Autodesk Fusion 360 part; units mm, degrees
(part 3 of 6)
sketch "Skizze5" plane through (0, 0, 0) normal (0, 1, 0) x (1, 0, 0)
  spline S0 degree 5 poles (100, -0.054) (99.9703, -0.0563) (99.9084, -0.0613) (99.8079, -0.0698) (99.6587, -0.0835) (99.4472, -0.1042) (99.2124, -0.1285) (98.957, -0.1559) (98.6857, -0.1861) (98.4034, -0.2184) (98.1151, -0.2525) (97.8247, -0.2876) (97.5347, -0.3237) (97.2456, -0.3604) (96.957, -0.3978) (96.6678, -0.4359) (96.3769, -0.4747) (96.0836, -0.5141) (95.788, -0.5542) (95.4904, -0.5949) (95.1918, -0.6361) (94.8927, -0.6777) (94.594, -0.7196) (94.2958, -0.7618) (93.9981, -0.8044) (93.7007, -0.8473) (93.4032, -0.8905) (93.1053, -0.9341) (92.8069, -0.978) (92.508, -1.0221) (92.2086, -1.0663) (91.9089, -1.1107) (91.6091, -1.1551) (91.3092, -1.1996) (91.0094, -1.244) (90.7096, -1.2886) (90.4099, -1.3332) (90.1102, -1.3779) (89.8105, -1.4227) (89.5107, -1.4676) (89.2109, -1.5126) (88.9111, -1.5576) (88.6111, -1.6025) (88.3111, -1.6473) (88.0111, -1.692) (87.711, -1.7366) (87.411, -1.7811) (87.1111, -1.8255) (86.8112, -1.8699) (86.5115, -1.9143) (86.2119, -1.9587) (85.9124, -2.003) (85.613, -2.0472) (85.3136, -2.0913) (85.0142, -2.1353) (84.7147, -2.179) (84.4152, -2.2226) (84.1157, -2.2661) (83.8162, -2.3094) (83.5167, -2.3526) (83.2173, -2.3957) (82.9178, -2.4387) (82.6184, -2.4816) (82.3189, -2.5243) (82.0196, -2.5668) (81.7202, -2.6092) (81.4208, -2.6513) (81.1215, -2.6933) (80.8222, -2.7352) (80.5229, -2.7769) (80.2237, -2.8184) (79.9245, -2.8598) (79.6253, -2.901) (79.3262, -2.9421) (79.027, -2.9829) (78.7278, -3.0236) (78.4286, -3.0639) (78.1294, -3.1041) (77.8302, -3.1439) (77.5309, -3.1835) (77.2316, -3.2228) (76.9322, -3.2619) (76.6329, -3.3007) (76.3335, -3.3393) (76.0342, -3.3777) (75.7348, -3.4159) (75.4355, -3.454) (75.1362, -3.4919) (74.8369, -3.5295) (74.5376, -3.567) (74.2382, -3.6042) (73.9389, -3.6412) (73.6395, -3.6778) (73.3402, -3.7141) (73.0407, -3.7501) (72.7413, -3.7859) (72.4419, -3.8214) (72.1425, -3.8568) (71.843, -3.8919) (71.5436, -3.9268) (71.2441, -3.9615) (70.9446, -3.9959) (70.6451, -4.0299) (70.3455, -4.0636) (70.0458, -4.097) (69.7461, -4.13) (69.4464, -4.1628) (69.1467, -4.1953) (68.8471, -4.2275) (68.5474, -4.2596) (68.2478, -4.2915) (67.9482, -4.3232) (67.6485, -4.3546) (67.3489, -4.3857) (67.0492, -4.4166) (66.7494, -4.4472) (66.4496, -4.4775) (66.1497, -4.5074) (65.8499, -4.5371) (65.5499, -4.5664) (65.25, -4.5954) (64.95, -4.6241) (64.65, -4.6525) (64.35, -4.6806) (64.05, -4.7084) (63.7499, -4.736) (63.4498, -4.7633) (63.1496, -4.7903) (62.8494, -4.8171) (62.5492, -4.8436) (62.249, -4.8699) (61.9487, -4.8959) (61.6484, -4.9216) (61.3481, -4.947) (61.0477, -4.972) (60.7474, -4.9968) (60.447, -5.0214) (60.1465, -5.0456) (59.8461, -5.0696) (59.5456, -5.0934) (59.245, -5.117) (58.9445, -5.1403) (58.6439, -5.1635) (58.3433, -5.1863) (58.0426, -5.2089) (57.742, -5.2312) (57.4414, -5.2531) (57.1408, -5.2747) (56.8401, -5.2959) (56.5395, -5.3169) (56.2388, -5.3376) (55.9381, -5.3581) (55.6373, -5.3784) (55.3364, -5.3985) (55.0355, -5.4183) (54.7346, -5.4379) (54.4336, -5.4572) (54.1326, -5.4762) (53.8316, -5.4949) (53.5305, -5.5134) (53.2295, -5.5315) (52.9284, -5.5494) (52.6274, -5.567) (52.3263, -5.5845) (52.0252, -5.6017) (51.7241, -5.6187) (51.4231, -5.6355) (51.122, -5.652) (50.8209, -5.6684) (50.5198, -5.6844) (50.2187, -5.7003) (49.9176, -5.7158) (49.6165, -5.7311) (49.3153, -5.746) (49.0141, -5.7607) (48.7129, -5.7751) (48.4116, -5.7892) (48.1104, -5.8031) (47.8091, -5.8168) (47.5078, -5.8303) (47.2065, -5.8435) (46.9052, -5.8565) (46.604, -5.8692) (46.3027, -5.8817) (46.0015, -5.8939) (45.7003, -5.9058) (45.3991, -5.9174) (45.0979, -5.9287) (44.7967, -5.9397) (44.4955, -5.9505) (44.1943, -5.961) (43.893, -5.9713) (43.5918, -5.9813) (43.2906, -5.9909) (42.9893, -6.0004) (42.6882, -6.0095) (42.387, -6.0183) (42.0858, -6.0269) (41.7847, -6.0352) (41.4836, -6.0433) (41.1824, -6.0511) (40.8813, -6.0587) (40.5801, -6.066) (40.2789, -6.0729) (39.9777, -6.0796) (39.6765, -6.0859) (39.3753, -6.0918) (39.0741, -6.0973) (38.773, -6.1025) (38.472, -6.1074) (38.171, -6.1119) (37.87, -6.1161) (37.5691, -6.1201) (37.2683, -6.1237) (36.9675, -6.1271) (36.6667, -6.1302) (36.366, -6.133) (36.0651, -6.1355) (35.7643, -6.1377) (35.4635, -6.1395) (35.1626, -6.141) (34.8617, -6.142) (34.5609, -6.1427) (34.2601, -6.1431) (33.9593, -6.143) (33.6586, -6.1425) (33.3579, -6.1416) (33.0573, -6.1404) (32.7568, -6.1387) (32.4563, -6.1367) (32.1559, -6.1344) (31.8555, -6.1316) (31.5551, -6.1285) (31.2547, -6.1251) (30.9543, -6.1212) (30.6539, -6.117) (30.3536, -6.1123) (30.0532, -6.1072) (29.753, -6.1018) (29.4528, -6.0959) (29.1527, -6.0895) (28.8527, -6.0828) (28.5528, -6.0756) (28.2529, -6.068) (27.9532, -6.0599) (27.6535, -6.0513) (27.3539, -6.0423) (27.0543, -6.0328) (26.7548, -6.0228) (26.4552, -6.0123) (26.1558, -6.0013) (25.8563, -5.9898) (25.5569, -5.9778) (25.2576, -5.9654) (24.9584, -5.9525) (24.6592, -5.9391) (24.3602, -5.9253) (24.0612, -5.9109) (23.7624, -5.8959) (23.4637, -5.8804) (23.1651, -5.8644) (22.8665, -5.8477) (22.5681, -5.8305) (22.2698, -5.8126) (21.9715, -5.7942) (21.6734, -5.7753) (21.3754, -5.7557) (21.0774, -5.7355) (20.7797, -5.7147) (20.482, -5.6932) (20.1846, -5.671) (19.8873, -5.6481) (19.5901, -5.6246) (19.2931, -5.6003) (18.9963, -5.5754) (18.6995, -5.5498) (18.4029, -5.5235) (18.1065, -5.4966) (17.8102, -5.469) (17.5142, -5.4407) (17.2183, -5.4117) (16.9227, -5.382) (16.6273, -5.3515) (16.3321, -5.3202) (16.0372, -5.288) (15.7425, -5.2549) (15.448, -5.2209) (15.1538, -5.1859) (14.8598, -5.1501) (14.5661, -5.1133) (14.2728, -5.0756) (13.9798, -5.0371) (13.6871, -4.9976) (13.3949, -4.9573) (13.103, -4.916) (12.8115, -4.8736) (12.5204, -4.8302) (12.2297, -4.7856) (11.9395, -4.7399) (11.6496, -4.693) (11.3603, -4.6448) (11.0714, -4.5954) (10.783, -4.5448) (10.4951, -4.493) (10.2078, -4.4398) (9.9211, -4.3854) (9.635, -4.3296) (9.3496, -4.2725) (9.0648, -4.2139) (8.7808, -4.1539) (8.4976, -4.0924) (8.2153, -4.0294) (7.9338, -3.9647) (7.6534, -3.8984) (7.3739, -3.8304) (7.0956, -3.7608) (6.8184, -3.6893) (6.5424, -3.6161) (6.2678, -3.541) (5.9946, -3.4641) (5.7231, -3.3853) (5.4534, -3.3045) (5.1857, -3.2217) (4.9202, -3.1368) (4.6572, -3.0499) (4.397, -2.9607) (4.14, -2.8693) (3.8864, -2.7758) (3.6367, -2.6801) (3.3914, -2.5824) (3.151, -2.4829) (2.9161, -2.3818) (2.6874, -2.2791) (2.4655, -2.1752) (2.2513, -2.07) (2.0455, -1.9637) (1.8488, -1.8566) (1.6618, -1.7492) (1.4847, -1.6421) (1.3178, -1.5359) (1.1612, -1.431) (1.0149, -1.327) (0.8788, -1.2233) (0.7528, -1.1197) (0.6367, -1.0169) (0.5301, -0.9168) (0.4329, -0.8201) (0.3448, -0.7236) (0.2659, -0.6222) (0.1959, -0.5179) (0.1349, -0.4238) (0.0831, -0.343) (0.0417, -0.2446) (0.0126, -0.1127) (-0.0013, -0.0224) (-0.001, -0.018) (0.0022, 0.06) (0.021, 0.1744) (0.0653, 0.2622) (0.1271, 0.3406) (0.1997, 0.4227) (0.2828, 0.5032) (0.3764, 0.5771) (0.4797, 0.647) (0.5918, 0.7165) (0.7127, 0.7861) (0.8428, 0.8551) (0.9827, 0.9229) (1.1327, 0.9898) (1.2933, 1.0565) (1.4646, 1.1233) (1.6468, 1.1901) (1.84, 1.2567) (2.0439, 1.3229) (2.2581, 1.3884) (2.4819, 1.4528) (2.7147, 1.5161) (2.9555, 1.5779) (3.2036, 1.6382) (3.458, 1.6968) (3.7179, 1.7536) (3.9826, 1.8086) (4.2513, 1.8617) (4.5235, 1.9129) (4.7987, 1.9623) (5.0764, 2.0098) (5.3563, 2.0557) (5.638, 2.0999) (5.9214, 2.1425) (6.2062, 2.1835) (6.4923, 2.2231) (6.7794, 2.2611) (7.0676, 2.2978) (7.3567, 2.3332) (7.6466, 2.3672) (7.9373, 2.4) (8.2287, 2.4315) (8.5207, 2.4619) (8.8133, 2.4912) (9.1065, 2.5193) (9.4001, 2.5464) (9.6942, 2.5725) (9.9887, 2.5976) (10.2836, 2.6218) (10.5789, 2.645) (10.8745, 2.6675) (11.1705, 2.6892) (11.4667, 2.7101) (11.7632, 2.7304) (12.06, 2.7499) (12.3571, 2.7687) (12.6543, 2.7867) (12.9518, 2.804) (13.2495, 2.8206) (13.5474, 2.8365) (13.8455, 2.8516) (14.1438, 2.8662) (14.4423, 2.8801) (14.7409, 2.8934) (15.0398, 2.9062) (15.3388, 2.9185) (15.6379, 2.9304) (15.9371, 2.9418) (16.2365, 2.9527) (16.5359, 2.9633) (16.8355, 2.9733) (17.1351, 2.983) (17.4349, 2.9921) (17.7347, 3.0008) (18.0347, 3.009) (18.3348, 3.0168) (18.6351, 3.0241) (18.9354, 3.031) (19.2358, 3.0375) (19.5364, 3.0436) (19.837, 3.0494) (20.1377, 3.0548) (20.4384, 3.0599) (20.7393, 3.0646) (21.0401, 3.0689) (21.3411, 3.0728) (21.642, 3.0764) (21.943, 3.0797) (22.2441, 3.0827) (22.5452, 3.0855) (22.8464, 3.0881) (23.1477, 3.0904) (23.449, 3.0924) (23.7503, 3.0941) (24.0517, 3.0954) (24.3531, 3.0964) (24.6546, 3.0971) (24.956, 3.0974) (25.2575, 3.0975) (25.5591, 3.0973) (25.8606, 3.097) (26.1622, 3.0966) (26.4639, 3.096) (26.7655, 3.0952) (27.0673, 3.0941) (27.369, 3.0927) (27.6708, 3.091) (27.9726, 3.089) (28.2745, 3.0867) (28.5764, 3.0841) (28.8783, 3.0814) (29.1802, 3.0785) (29.4821, 3.0755) (29.7841, 3.0724) (30.086, 3.0691) (30.388, 3.0656) (30.69, 3.062) (30.992, 3.058) (31.294, 3.0539) (31.596, 3.0495) (31.8981, 3.0449) (32.2001, 3.0402) (32.5022, 3.0353) (32.8043, 3.0303) (33.1064, 3.0251) (33.4086, 3.0198) (33.7107, 3.0142) (34.0129, 3.0084) (34.315, 3.0024) (34.6172, 2.9962) (34.9194, 2.9897) (35.2217, 2.9831) (35.5239, 2.9763) (35.8262, 2.9694) (36.1284, 2.9624) (36.4307, 2.9553) (36.733, 2.9481) (37.0353, 2.9407) (37.3377, 2.9333) (37.64, 2.9257) (37.9424, 2.9179) (38.2448, 2.91) (38.5472, 2.9019) (38.8496, 2.8937) (39.1519, 2.8853) (39.4543, 2.8767) (39.7567, 2.8679) (40.0591, 2.859) (40.3614, 2.8499) (40.6638, 2.8406) (40.9661, 2.8312) (41.2684, 2.8217) (41.5708, 2.812) (41.8731, 2.8023) (42.1755, 2.7926) (42.4779, 2.7828) (42.7804, 2.7729) (43.0828, 2.7628) (43.3853, 2.7526) (43.6877, 2.7422) (43.9902, 2.7316) (44.2926, 2.7207) (44.595, 2.7097) (44.8974, 2.6986) (45.1998, 2.6873) (45.5023, 2.6761) (45.8047, 2.6648) (46.1072, 2.6535) (46.4097, 2.6422) (46.7122, 2.6307) (47.0148, 2.6191) (47.3174, 2.6073) (47.62, 2.5953) (47.9226, 2.5832) (48.2252, 2.5709) (48.5278, 2.5586) (48.8303, 2.5462) (49.1329, 2.5338) (49.4355, 2.5214) (49.738, 2.5089) (50.0406, 2.4963) (50.3432, 2.4837) (50.6459, 2.4708) (50.9485, 2.4579) (51.2512, 2.4448) (51.5539, 2.4317) (51.8565, 2.4185) (52.1592, 2.4052) (52.4618, 2.3919) (52.7645, 2.3785) (53.0671, 2.3651) (53.3698, 2.3516) (53.6725, 2.338) (53.9752, 2.3242) (54.2779, 2.3103) (54.5806, 2.2963) (54.8834, 2.2823) (55.1861, 2.2681) (55.4889, 2.2539) (55.7916, 2.2397) (56.0944, 2.2254) (56.3971, 2.211) (56.6998, 2.1966) (57.0025, 2.182) (57.3052, 2.1674) (57.6079, 2.1527) (57.9106, 2.138) (58.2134, 2.1232) (58.5161, 2.1084) (58.8188, 2.0936) (59.1216, 2.0788) (59.4244, 2.0639) (59.7272, 2.049) (60.03, 2.034) (60.3329, 2.019) (60.6358, 2.0038) (60.9387, 1.9886) (61.2416, 1.9733) (61.5445, 1.9579) (61.8474, 1.9426) (62.1502, 1.9272) (62.4531, 1.9119) (62.7558, 1.8965) (63.0586, 1.881) (63.3614, 1.8655) (63.6642, 1.8498) (63.967, 1.8341) (64.2698, 1.8182) (64.5727, 1.8024) (64.8756, 1.7865) (65.1786, 1.7706) (65.4815, 1.7548) (65.7845, 1.739) (66.0875, 1.7233) (66.3905, 1.7075) (66.6935, 1.6916) (66.9964, 1.6757) (67.2993, 1.6596) (67.6021, 1.6435) (67.905, 1.6273) (68.2078, 1.611) (68.5107, 1.5946) (68.8136, 1.5782) (69.1165, 1.5619) (69.4195, 1.5455) (69.7225, 1.5291) (70.0255, 1.5127) (70.3284, 1.4964) (70.6314, 1.48) (70.9344, 1.4637) (71.2373, 1.4473) (71.5403, 1.4309) (71.8432, 1.4145) (72.1462, 1.3981) (72.4491, 1.3816) (72.7521, 1.365) (73.055, 1.3484) (73.358, 1.3318) (73.6609, 1.3151) (73.9638, 1.2984) (74.2667, 1.2816) (74.5697, 1.2649) (74.8726, 1.2481) (75.1757, 1.2314) (75.4787, 1.2146) (75.7818, 1.1979) (76.0848, 1.1812) (76.3879, 1.1645) (76.6909, 1.1477) (76.9938, 1.1309) (77.2968, 1.1141) (77.5997, 1.0972) (77.9026, 1.0803) (78.2055, 1.0633) (78.5085, 1.0462) (78.8116, 1.029) (79.1148, 1.0119) (79.4179, 0.9948) (79.7211, 0.9777) (80.0242, 0.9607) (80.3273, 0.9437) (80.6304, 0.9268) (80.9334, 0.9099) (81.2364, 0.893) (81.5394, 0.8761) (81.8424, 0.8591) (82.1455, 0.8421) (82.4485, 0.825) (82.7516, 0.8079) (83.0546, 0.7907) (83.3576, 0.7736) (83.6605, 0.7565) (83.9634, 0.7394) (84.2662, 0.7225) (84.569, 0.7056) (84.8718, 0.6888) (85.1746, 0.6721) (85.4774, 0.6555) (85.7802, 0.639) (86.083, 0.6224) (86.3857, 0.6059) (86.6884, 0.5894) (86.9911, 0.5729) (87.2937, 0.5565) (87.5962, 0.54) (87.8988, 0.5237) (88.2013, 0.5074) (88.5039, 0.4912) (88.8064, 0.4752) (89.1088, 0.4593) (89.4111, 0.4435) (89.7132, 0.4278) (90.0152, 0.4123) (90.3171, 0.3969) (90.619, 0.3816) (90.9208, 0.3665) (91.2228, 0.3515) (91.525, 0.3367) (91.8272, 0.322) (92.1294, 0.3075) (92.4314, 0.2932) (92.733, 0.2791) (93.0342, 0.2652) (93.3348, 0.2515) (93.6352, 0.2381) (93.9355, 0.2249) (94.2361, 0.212) (94.5372, 0.1993) (94.8388, 0.187) (95.1408, 0.175) (95.4424, 0.1633) (95.7428, 0.1521) (96.0413, 0.1412) (96.3374, 0.1308) (96.6311, 0.1209) (96.9232, 0.1115) (97.2149, 0.1027) (97.5075, 0.0944) (97.8012, 0.0868) (98.0954, 0.0797) (98.3877, 0.0734) (98.6739, 0.0678) (98.9487, 0.0631) (99.2071, 0.0593) (99.4444, 0.0564) (99.6576, 0.0545) (99.8076, 0.0538) (99.9084, 0.0537) (99.9703, 0.0539) (100, 0.054) knots 0 0 0 0 0 0 0.00142857 0.00285714 0.00428571 0.00571429 0.00714286 0.00857143 0.01 0.01142857 0.01285714 0.01428571 0.01571429 0.01714286 0.01857143 0.02 0.02142857 0.02285714 0.02428571 0.02571429 0.02714286 0.02857143 0.03 0.03142857 0.03285714 0.03428571 0.03571429 0.03714286 0.03857143 0.04 0.04142857 0.04285714 0.04428571 0.04571429 0.04714286 0.04857143 0.05 0.05142857 0.05285714 0.05428571 0.05571429 0.05714286 0.05857143 0.06 0.06142857 0.06285714 0.06428571 0.06571429 0.06714286 0.06857143 0.07 0.07142857 0.07285714 0.07428571 0.07571429 0.07714286 0.07857143 0.08 0.08142857 0.08285714 0.08428571 0.08571429 0.08714286 0.08857143 0.09 0.09142857 0.09285714 0.09428571 0.09571429 0.09714286 0.09857143 0.1 0.10142857 0.10285714 0.10428571 0.10571429 0.10714286 0.10857143 0.11 0.11142857 0.11285714 0.11428571 0.11571429 0.11714286 0.11857143 0.12 0.12142857 0.12285714 0.12428571 0.12571429 0.12714286 0.12857143 0.13 0.13142857 0.13285714 0.13428571 0.13571429 0.13714286 0.13857143 0.14 0.14142857 0.14285714 0.14428571 0.14571429 0.14714286 0.14857143 0.15 0.15142857 0.15285714 0.15428571 0.15571429 0.15714286 0.15857143 0.16 0.16142857 0.16285714 0.16428571 0.16571429 0.16714286 0.16857143 0.17 0.17142857 0.17285714 0.17428571 0.17571429 0.17714286 0.17857143 0.18 0.18142857 0.18285714 0.18428571 0.18571429 0.18714286 0.18857143 0.19 0.19142857 0.19285714 0.19428571 0.19571429 0.19714286 0.19857143 0.2 0.20142857 0.20285714 0.20428571 0.20571429 0.20714286 0.20857143 0.21 0.21142857 0.21285714 0.21428571 0.21571429 0.21714286 0.21857143 0.22 0.22142857 0.22285714 0.22428571 0.22571429 0.22714286 0.22857143 0.23 0.23142857 0.23285714 0.23428571 0.23571429 0.23714286 0.23857143 0.24 0.24142857 0.24285714 0.24428571 0.24571429 0.24714286 0.24857143 0.25 0.25142857 0.25285714 0.25428571 0.25571429 0.25714286 0.25857143 0.26 0.26142857 0.26285714 0.26428571 0.26571429 0.26714286 0.26857143 0.27 0.27142857 0.27285714 0.27428571 0.27571429 0.27714286 0.27857143 0.28 0.28142857 0.28285714 0.28428571 0.28571429 0.28714286 0.28857143 0.29 0.29142857 0.29285714 0.29428571 0.29571429 0.29714286 0.29857143 0.3 0.30142857 0.30285714 0.30428571 0.30571429 0.30714286 0.30857143 0.31 0.31142857 0.31285714 0.31428571 0.31571429 0.31714286 0.31857143 0.32 0.32142857 0.32285714 0.32428571 0.32571429 0.32714286 0.32857143 0.33 0.33142857 0.33285714 0.33428571 0.33571429 0.33714286 0.33857143 0.34 0.34142857 0.34285714 0.34428571 0.34571429 0.34714286 0.34857143 0.35 0.35142857 0.35285714 0.35428571 0.35571429 0.35714286 0.35857143 0.36 0.36142857 0.36285714 0.36428571 0.36571429 0.36714286 0.36857143 0.37 0.37142857 0.37285714 0.37428571 0.37571429 0.37714286 0.37857143 0.38 0.38142857 0.38285714 0.38428571 0.38571429 0.38714286 0.38857143 0.39 0.39142857 0.39285714 0.39428571 0.39571429 0.39714286 0.39857143 0.4 0.40142857 0.40285714 0.40428571 0.40571429 0.40714286 0.40857143 0.41 0.41142857 0.41285714 0.41428571 0.41571429 0.41714286 0.41857143 0.42 0.42142857 0.42285714 0.42428571 0.42571429 0.42714286 0.42857143 0.43 0.43142857 0.43285714 0.43428571 0.43571429 0.43714286 0.43857143 0.44 0.44142857 0.44285714 0.44428571 0.44571429 0.44714286 0.44857143 0.45 0.45142857 0.45285714 0.45428571 0.45571429 0.45714286 0.45857143 0.46 0.46142857 0.46285714 0.46428571 0.46571429 0.46714286 0.46857143 0.47 0.47142857 0.47285714 0.47428571 0.47571429 0.47714286 0.47857143 0.48 0.48142857 0.48285714 0.48428571 0.48571429 0.48714286 0.48857143 0.49 0.49142857 0.49285714 0.49428571 0.49571429 0.49714286 0.49857143 0.5 0.50142857 0.50285714 0.50428571 0.50571429 0.50714286 0.50857143 0.51 0.51142857 0.51285714 0.51428571 0.51571429 0.51714286 0.51857143 0.52 0.52142857 0.52285714 0.52428571 0.52571429 0.52714286 0.52857143 0.53 0.53142857 0.53285714 0.53428571 0.53571429 0.53714286 0.53857143 0.54 0.54142857 0.54285714 0.54428571 0.54571429 0.54714286 0.54857143 0.55 0.55142857 0.55285714 0.55428571 0.55571429 0.55714286 0.55857143 0.56 0.56142857 0.56285714 0.56428571 0.56571429 0.56714286 0.56857143 0.57 0.57142857 0.57285714 0.57428571 0.57571429 0.57714286 0.57857143 0.58 0.58142857 0.58285714 0.58428571 0.58571429 0.58714286 0.58857143 0.59 0.59142857 0.59285714 0.59428571 0.59571429 0.59714286 0.59857143 0.6 0.60142857 0.60285714 0.60428571 0.60571429 0.60714286 0.60857143 0.61 0.61142857 0.61285714 0.61428571 0.61571429 0.61714286 0.61857143 0.62 0.62142857 0.62285714 0.62428571 0.62571429 0.62714286 0.62857143 0.63 0.63142857 0.63285714 0.63428571 0.63571429 0.63714286 0.63857143 0.64 0.64142857 0.64285714 0.64428571 0.64571429 0.64714286 0.64857143 0.65 0.65142857 0.65285714 0.65428571 0.65571429 0.65714286 0.65857143 0.66 0.66142857 0.66285714 0.66428571 0.66571429 0.66714286 0.66857143 0.67 0.67142857 0.67285714 0.67428571 0.67571429 0.67714286 0.67857143 0.68 0.68142857 0.68285714 0.68428571 0.68571429 0.68714286 0.68857143 0.69 0.69142857 0.69285714 0.69428571 0.69571429 0.69714286 0.69857143 0.7 0.70142857 0.70285714 0.70428571 0.70571429 0.70714286 0.70857143 0.71 0.71142857 0.71285714 0.71428571 0.71571429 0.71714286 0.71857143 0.72 0.72142857 0.72285714 0.72428571 0.72571429 0.72714286 0.72857143 0.73 0.73142857 0.73285714 0.73428571 0.73571429 0.73714286 0.73857143 0.74 0.74142857 0.74285714 0.74428571 0.74571429 0.74714286 0.74857143 0.75 0.75142857 0.75285714 0.75428571 0.75571429 0.75714286 0.75857143 0.76 0.76142857 0.76285714 0.76428571 0.76571429 0.76714286 0.76857143 0.77 0.77142857 0.77285714 0.77428571 0.77571429 0.77714286 0.77857143 0.78 0.78142857 0.78285714 0.78428571 0.78571429 0.78714286 0.78857143 0.79 0.79142857 0.79285714 0.79428571 0.79571429 0.79714286 0.79857143 0.8 0.80142857 0.80285714 0.80428571 0.80571429 0.80714286 0.80857143 0.81 0.81142857 0.81285714 0.81428571 0.81571429 0.81714286 0.81857143 0.82 0.82142857 0.82285714 0.82428571 0.82571429 0.82714286 0.82857143 0.83 0.83142857 0.83285714 0.83428571 0.83571429 0.83714286 0.83857143 0.84 0.84142857 0.84285714 0.84428571 0.84571429 0.84714286 0.84857143 0.85 0.85142857 0.85285714 0.85428571 0.85571429 0.85714286 0.85857143 0.86 0.86142857 0.86285714 0.86428571 0.86571429 0.86714286 0.86857143 0.87 0.87142857 0.87285714 0.87428571 0.87571429 0.87714286 0.87857143 0.88 0.88142857 0.88285714 0.88428571 0.88571429 0.88714286 0.88857143 0.89 0.89142857 0.89285714 0.89428571 0.89571429 0.89714286 0.89857143 0.9 0.90142857 0.90285714 0.90428571 0.90571429 0.90714286 0.90857143 0.91 0.91142857 0.91285714 0.91428571 0.91571429 0.91714286 0.91857143 0.92 0.92142857 0.92285714 0.92428571 0.92571429 0.92714286 0.92857143 0.93 0.93142857 0.93285714 0.93428571 0.93571429 0.93714286 0.93857143 0.94 0.94142857 0.94285714 0.94428571 0.94571429 0.94714286 0.94857143 0.95 0.95142857 0.95285714 0.95428571 0.95571429 0.95714286 0.95857143 0.96 0.96142857 0.96285714 0.96428571 0.96571429 0.96714286 0.96857143 0.97 0.97142857 0.97285714 0.97428571 0.97571429 0.97714286 0.97857143 0.98 0.98142857 0.98285714 0.98428571 0.98571429 0.98714286 0.98857143 0.99 0.99142857 0.99285714 0.99428571 0.99571429 0.99714286 0.99857143 1 1 1 1 1 1
  line L0 (100, 0.054) -> (100, -0.054)
  point P0 (99.325, -0.117)
  point P1 (97.996, -0.267)
  point P2 (96.48, -0.461)
  point P3 (94.891, -0.678)
  point P4 (93.284, -0.908)
  point P5 (91.664, -1.147)
  point P6 (90.036, -1.389)
  point P7 (88.407, -1.633)
  point P8 (86.777, -1.875)
  point P9 (85.152, -2.115)
  point P10 (83.528, -2.351)
  point P11 (81.905, -2.583)
  point P12 (80.284, -2.81)
  point P13 (78.665, -3.032)
  point P14 (77.046, -3.247)
  point P15 (75.427, -3.455)
  point P16 (73.809, -3.657)
  point P17 (72.191, -3.851)
  point P18 (70.573, -4.038)
  point P19 (68.954, -4.216)
  point P20 (67.336, -4.387)
  point P21 (65.717, -4.55)
  point P22 (64.097, -4.704)
  point P23 (62.476, -4.85)
  point P24 (60.854, -4.988)
  point P25 (59.231, -5.118)
  point P26 (57.607, -5.241)
  point P27 (55.983, -5.355)
  point P28 (54.357, -5.462)
  point P29 (52.73, -5.561)
  point P30 (51.103, -5.653)
  point P31 (49.476, -5.738)
  point P32 (47.848, -5.815)
  point P33 (46.22, -5.885)
  point P34 (44.593, -5.947)
  point P35 (42.966, -6.001)
  point P36 (41.34, -6.047)
  point P37 (39.714, -6.085)
  point P38 (38.089, -6.113)
  point P39 (36.467, -6.132)
  point P40 (34.845, -6.142)
  point P41 (33.224, -6.141)
  point P42 (31.606, -6.129)
  point P43 (29.989, -6.106)
  point P44 (28.375, -6.071)
  point P45 (26.765, -6.023)
  point P46 (25.157, -5.961)
  point P47 (23.553, -5.885)
  point P48 (21.954, -5.793)
  point P49 (20.36, -5.684)
  point P50 (18.773, -5.556)
  point P51 (17.193, -5.409)
  point P52 (15.623, -5.241)
  point P53 (14.064, -5.048)
  point P54 (12.521, -4.83)
  point P55 (10.996, -4.582)
  point P56 (9.493, -4.301)
  point P57 (8.019, -3.984)
  point P58 (6.585, -3.627)
  point P59 (5.208, -3.228)
  point P60 (3.924, -2.789)
  point P61 (2.793, -2.326)
  point P62 (1.888, -1.877)
  point P63 (1.237, -1.481)
  point P64 (0.791, -1.15)
  point P65 (0.486, -0.872)
  point P66 (0.275, -0.631)
  point P67 (0.131, -0.417)
  point P68 (0.04, -0.221)
  point P69 (0.002, -0.041)
  point P70 (0.018, 0.135)
  point P71 (0.104, 0.309)
  point P72 (0.257, 0.476)
  point P73 (0.476, 0.643)
  point P74 (0.778, 0.82)
  point P75 (1.202, 1.018)
  point P76 (1.82, 1.249)
  point P77 (2.714, 1.515)
  point P78 (3.89, 1.789)
  point P79 (5.256, 2.039)
  point P80 (6.72, 2.253)
  point P81 (8.236, 2.432)
  point P82 (9.784, 2.58)
  point P83 (11.353, 2.702)
  point P84 (12.937, 2.803)
  point P85 (14.532, 2.884)
  point P86 (16.136, 2.949)
  point P87 (17.746, 3.001)
  point P88 (19.362, 3.04)
  point P89 (20.983, 3.068)
  point P90 (22.607, 3.086)
  point P91 (24.234, 3.096)
  point P92 (25.863, 3.097)
  point P93 (27.494, 3.092)
  point P94 (29.127, 3.079)
  point P95 (30.761, 3.061)
  point P96 (32.396, 3.037)
  point P97 (34.032, 3.008)
  point P98 (35.669, 2.973)
  point P99 (37.307, 2.934)
  point P100 (38.946, 2.891)
  point P101 (40.585, 2.843)
  point P102 (42.224, 2.791)
  point P103 (43.864, 2.736)
  point P104 (45.504, 2.676)
  point P105 (47.145, 2.614)
  point P106 (48.787, 2.548)
  point P107 (50.429, 2.48)
  point P108 (52.072, 2.409)
  point P109 (53.715, 2.336)
  point P110 (55.359, 2.26)
  point P111 (57.003, 2.182)
  point P112 (58.647, 2.102)
  point P113 (60.292, 2.021)
  point P114 (61.938, 1.938)
  point P115 (63.583, 1.854)
  point P116 (65.229, 1.768)
  point P117 (66.876, 1.682)
  point P118 (68.522, 1.594)
  point P119 (70.169, 1.505)
  point P120 (71.816, 1.416)
  point P121 (73.463, 1.326)
  point P122 (75.11, 1.235)
  point P123 (76.758, 1.144)
  point P124 (78.405, 1.052)
  point P125 (80.054, 0.959)
  point P126 (81.702, 0.867)
  point P127 (83.35, 0.774)
  point P128 (84.996, 0.682)
  point P129 (86.641, 0.592)
  point P130 (88.284, 0.503)
  point P131 (89.924, 0.417)
  point P132 (91.56, 0.335)
  point P133 (93.193, 0.258)
  point P134 (94.816, 0.188)
  point P135 (96.423, 0.128)
  point P136 (97.962, 0.083)
  point P137 (99.319, 0.058)
surface "Profilschnitt_R1" add patch profiles "Skizze5" section 1 separate body makes body 5
scale "Profiltiefe_R1" factor 2.55 about (0, 0, 0) bodies 5
move_body "Station_R1" bodies 5 to x (1, 0, 0) y (0, 1, 0) z (0, 0, 1) at (0, 60, 0)
sketch "Skizze6" plane through (0, 0, 0) normal (0, 1, 0) x (1, 0, 0)
  spline S0 degree 5 poles (100, -0.079) (99.9701, -0.0818) (99.9078, -0.0877) (99.8067, -0.0976) (99.657, -0.1128) (99.4452, -0.1351) (99.2102, -0.1605) (98.9548, -0.1887) (98.6833, -0.2193) (98.4004, -0.2518) (98.111, -0.2858) (97.8191, -0.3207) (97.527, -0.3562) (97.2355, -0.3922) (96.9443, -0.4285) (96.6525, -0.4653) (96.359, -0.5023) (96.0633, -0.5398) (95.7651, -0.5776) (95.4651, -0.6157) (95.1639, -0.6542) (94.8622, -0.6928) (94.5608, -0.7315) (94.2597, -0.7704) (93.9591, -0.8094) (93.6589, -0.8484) (93.3586, -0.8874) (93.058, -0.9265) (92.7571, -0.9656) (92.4557, -1.0047) (92.1541, -1.0439) (91.8523, -1.0832) (91.5504, -1.1226) (91.2487, -1.162) (90.9472, -1.2014) (90.6458, -1.2409) (90.3445, -1.2803) (90.0433, -1.3196) (89.742, -1.3589) (89.4406, -1.3981) (89.1392, -1.4371) (88.8377, -1.4761) (88.5362, -1.5151) (88.2347, -1.554) (87.9332, -1.5928) (87.6317, -1.6317) (87.3304, -1.6706) (87.029, -1.7094) (86.7278, -1.7483) (86.4266, -1.7871) (86.1253, -1.8258) (85.8242, -1.8645) (85.523, -1.903) (85.2218, -1.9413) (84.9206, -1.9795) (84.6194, -2.0175) (84.3181, -2.0554) (84.0169, -2.0932) (83.7156, -2.1308) (83.4143, -2.1685) (83.1131, -2.2061) (82.8119, -2.2437) (82.5107, -2.2812) (82.2095, -2.3187) (81.9084, -2.356) (81.6073, -2.3931) (81.3063, -2.4301) (81.0053, -2.467) (80.7043, -2.5037) (80.4032, -2.5403) (80.1022, -2.5768) (79.8011, -2.6132) (79.5, -2.6496) (79.1988, -2.6858) (78.8976, -2.722) (78.5964, -2.758) (78.2953, -2.7938) (77.9941, -2.8294) (77.693, -2.8648) (77.3919, -2.9) (77.0908, -2.9351) (76.7897, -2.97) (76.4886, -3.0048) (76.1875, -3.0395) (75.8863, -3.0741) (75.5852, -3.1086) (75.284, -3.1429) (74.9827, -3.1772) (74.6815, -3.2112) (74.3803, -3.2452) (74.0791, -3.2789) (73.7779, -3.3126) (73.4767, -3.3461) (73.1757, -3.3794) (72.8746, -3.4126) (72.5736, -3.4455) (72.2726, -3.4783) (71.9715, -3.5109) (71.6704, -3.5433) (71.3692, -3.5754) (71.068, -3.6073) (70.7668, -3.639) (70.4655, -3.6706) (70.1643, -3.702) (69.863, -3.7332) (69.5618, -3.7642) (69.2605, -3.7951) (68.9593, -3.8259) (68.658, -3.8565) (68.3567, -3.887) (68.0554, -3.9173) (67.754, -3.9474) (67.4527, -3.9773) (67.1514, -4.007) (66.8502, -4.0365) (66.5489, -4.0657) (66.2477, -4.0948) (65.9464, -4.1237) (65.6452, -4.1523) (65.3439, -4.1809) (65.0425, -4.2092) (64.7412, -4.2374) (64.4397, -4.2653) (64.1383, -4.293) (63.8369, -4.3203) (63.5354, -4.3474) (63.234, -4.3742) (62.9325, -4.4008) (62.6311, -4.4272) (62.3296, -4.4535) (62.0281, -4.4797) (61.7266, -4.5058) (61.425, -4.5319) (61.1234, -4.5578) (60.8218, -4.5835) (60.5202, -4.6089) (60.2185, -4.634) (59.9169, -4.6587) (59.6152, -4.6831) (59.3136, -4.7073) (59.0119, -4.7312) (58.7103, -4.755) (58.4086, -4.7786) (58.1069, -4.8022) (57.8052, -4.8256) (57.5035, -4.8489) (57.2018, -4.872) (56.9002, -4.8949) (56.5985, -4.9176) (56.2968, -4.9401) (55.995, -4.9622) (55.6933, -4.9841) (55.3915, -5.0057) (55.0897, -5.0271) (54.7878, -5.0482) (54.4859, -5.0692) (54.184, -5.0899) (53.8821, -5.1106) (53.5802, -5.1311) (53.2783, -5.1515) (52.9765, -5.1717) (52.6746, -5.1917) (52.3727, -5.2115) (52.0708, -5.2309) (51.7688, -5.25) (51.4669, -5.2688) (51.165, -5.2873) (50.863, -5.3055) (50.561, -5.3236) (50.2591, -5.3415) (49.9571, -5.3592) (49.6551, -5.3768) (49.3531, -5.3942) (49.0511, -5.4114) (48.7492, -5.4283) (48.4473, -5.4451) (48.1454, -5.4617) (47.8435, -5.478) (47.5416, -5.4941) (47.2397, -5.51) (46.9377, -5.5257) (46.6358, -5.5411) (46.3339, -5.5563) (46.0319, -5.5712) (45.7299, -5.5858) (45.428, -5.6001) (45.126, -5.6141) (44.824, -5.6279) (44.522, -5.6414) (44.22, -5.6547) (43.918, -5.6677) (43.6161, -5.6805) (43.3142, -5.6931) (43.0123, -5.7055) (42.7104, -5.7176) (42.4085, -5.7295) (42.1066, -5.7411) (41.8047, -5.7524) (41.5029, -5.7635) (41.2011, -5.7742) (40.8992, -5.7846) (40.5974, -5.7946) (40.2955, -5.8044) (39.9937, -5.8138) (39.6919, -5.823) (39.3902, -5.8319) (39.0885, -5.8405) (38.7868, -5.8489) (38.4851, -5.8571) (38.1835, -5.865) (37.8819, -5.8725) (37.5803, -5.8797) (37.2788, -5.8866) (36.9772, -5.8931) (36.6757, -5.8992) (36.3741, -5.905) (36.0726, -5.9104) (35.7711, -5.9156) (35.4695, -5.9204) (35.168, -5.925) (34.8666, -5.9293) (34.5651, -5.9333) (34.2637, -5.937) (33.9623, -5.9404) (33.661, -5.9434) (33.3597, -5.946) (33.0584, -5.9483) (32.7572, -5.9501) (32.456, -5.9515) (32.1548, -5.9524) (31.8537, -5.9529) (31.5526, -5.9531) (31.2515, -5.9528) (30.9504, -5.9522) (30.6494, -5.9512) (30.3485, -5.9499) (30.0475, -5.9482) (29.7466, -5.9461) (29.4458, -5.9436) (29.145, -5.9407) (28.8442, -5.9373) (28.5435, -5.9336) (28.2429, -5.9294) (27.9424, -5.9248) (27.6419, -5.9197) (27.3415, -5.9143) (27.0412, -5.9084) (26.741, -5.902) (26.4408, -5.8951) (26.1407, -5.8877) (25.8407, -5.8797) (25.5407, -5.8711) (25.2407, -5.8621) (24.9408, -5.8525) (24.641, -5.8425) (24.3412, -5.832) (24.0416, -5.8211) (23.742, -5.8097) (23.4425, -5.7978) (23.1431, -5.7854) (22.8438, -5.7724) (22.5447, -5.7588) (22.2456, -5.7445) (21.9467, -5.7296) (21.648, -5.7141) (21.3493, -5.6979) (21.0508, -5.6811) (20.7525, -5.6637) (20.4543, -5.6456) (20.1562, -5.627) (19.8583, -5.6077) (19.5606, -5.5877) (19.263, -5.5672) (18.9656, -5.5459) (18.6684, -5.5239) (18.3713, -5.5011) (18.0744, -5.4776) (17.7777, -5.4533) (17.4812, -5.4281) (17.1849, -5.4022) (16.8888, -5.3754) (16.5929, -5.3479) (16.2973, -5.3196) (16.002, -5.2905) (15.707, -5.2606) (15.4122, -5.2298) (15.1177, -5.198) (14.8235, -5.1652) (14.5295, -5.1315) (14.2358, -5.0967) (13.9425, -5.0609) (13.6494, -5.0241) (13.3568, -4.9863) (13.0645, -4.9475) (12.7726, -4.9076) (12.4812, -4.8668) (12.1903, -4.8248) (11.8998, -4.7817) (11.6099, -4.7374) (11.3205, -4.6919) (11.0316, -4.6451) (10.7433, -4.597) (10.4555, -4.5475) (10.1683, -4.4967) (9.8818, -4.4445) (9.5959, -4.3909) (9.3107, -4.3358) (9.0263, -4.2794) (8.7426, -4.2214) (8.4599, -4.1619) (8.1781, -4.1008) (7.8973, -4.038) (7.6176, -3.9735) (7.3391, -3.9071) (7.0618, -3.839) (6.786, -3.7689) (6.5116, -3.6969) (6.2388, -3.623) (5.9678, -3.5472) (5.6986, -3.4695) (5.4315, -3.3897) (5.1666, -3.3078) (4.9042, -3.2237) (4.6446, -3.1373) (4.3879, -3.0486) (4.1346, -2.9576) (3.885, -2.8644) (3.6396, -2.769) (3.3988, -2.6717) (3.1631, -2.5726) (2.9332, -2.4717) (2.7096, -2.3694) (2.493, -2.2657) (2.2839, -2.161) (2.083, -2.0552) (1.8907, -1.9488) (1.7074, -1.8419) (1.5334, -1.735) (1.369, -1.6286) (1.2143, -1.5232) (1.0693, -1.4191) (0.934, -1.316) (0.8082, -1.2129) (0.6918, -1.1092) (0.5844, -1.0058) (0.4855, -0.9051) (0.3947, -0.8087) (0.3123, -0.7125) (0.2388, -0.6096) (0.1745, -0.5023) (0.1187, -0.4087) (0.0713, -0.3317) (0.0338, -0.2303) (0.0087, -0.0853) (-0.0021, -0.004) (-0.0007, -0.0204) (0.0044, 0.0795) (0.0265, 0.2057) (0.072, 0.289) (0.1329, 0.3635) (0.2038, 0.4498) (0.2851, 0.5349) (0.3772, 0.6098) (0.4783, 0.6797) (0.587, 0.7508) (0.7036, 0.8233) (0.829, 0.8947) (0.9638, 0.9637) (1.108, 1.031) (1.2616, 1.0977) (1.4247, 1.1643) (1.5975, 1.2308) (1.7805, 1.2969) (1.9736, 1.3623) (2.1766, 1.4267) (2.3892, 1.4899) (2.6108, 1.5518) (2.8408, 1.6123) (3.0785, 1.6712) (3.3234, 1.7284) (3.5747, 1.7837) (3.8317, 1.8372) (4.0938, 1.8889) (4.3604, 1.9386) (4.6308, 1.9864) (4.9046, 2.0324) (5.1812, 2.0766) (5.4603, 2.119) (5.7416, 2.1597) (6.0247, 2.1989) (6.3095, 2.2364) (6.5958, 2.2725) (6.8833, 2.3072) (7.1719, 2.3406) (7.4616, 2.3727) (7.7521, 2.4037) (8.0434, 2.4334) (8.3354, 2.462) (8.628, 2.4895) (8.9213, 2.5159) (9.2152, 2.5411) (9.5096, 2.5653) (9.8044, 2.5884) (10.0998, 2.6106) (10.3955, 2.6319) (10.6917, 2.6524) (10.9882, 2.6722) (11.285, 2.6913) (11.5821, 2.7097) (11.8795, 2.7274) (12.1771, 2.7445) (12.475, 2.7608) (12.7732, 2.7763) (13.0716, 2.7912) (13.3702, 2.8053) (13.669, 2.8188) (13.968, 2.8316) (14.2672, 2.8438) (14.5665, 2.8554) (14.866, 2.8665) (15.1656, 2.8771) (15.4653, 2.8873) (15.7652, 2.8971) (16.0651, 2.9065) (16.3652, 2.9154) (16.6655, 2.9239) (16.9658, 2.9318) (17.2663, 2.9393) (17.567, 2.9462) (17.8678, 2.9525) (18.1687, 2.9585) (18.4697, 2.964) (18.7707, 2.9692) (19.0719, 2.974) (19.3731, 2.9786) (19.6743, 2.9829) (19.9756, 2.9869) (20.277, 2.9905) (20.5784, 2.9937) (20.8799, 2.9966) (21.1814, 2.9991) (21.4831, 3.0012) (21.7849, 3.0031) (22.0867, 3.0047) (22.3886, 3.0061) (22.6906, 3.0073) (22.9927, 3.0082) (23.2948, 3.0088) (23.5969, 3.0091) (23.8989, 3.009) (24.201, 3.0086) (24.5031, 3.0078) (24.8052, 3.0068) (25.1074, 3.0055) (25.4096, 3.0041) (25.7119, 3.0026) (26.0143, 3.0009) (26.3167, 2.999) (26.6192, 2.9968) (26.9216, 2.9944) (27.2241, 2.9916) (27.5265, 2.9885) (27.829, 2.9851) (28.1314, 2.9815) (28.434, 2.9777) (28.7366, 2.9737) (29.0393, 2.9696) (29.342, 2.9655) (29.6448, 2.9611) (29.9476, 2.9566) (30.2504, 2.9518) (30.5532, 2.9468) (30.856, 2.9416) (31.1587, 2.9361) (31.4614, 2.9305) (31.7642, 2.9247) (32.067, 2.9188) (32.3699, 2.9129) (32.6728, 2.9068) (32.9758, 2.9006) (33.2788, 2.8942) (33.5817, 2.8876) (33.8847, 2.8808) (34.1876, 2.8737) (34.4905, 2.8664) (34.7934, 2.8589) (35.0963, 2.8513) (35.3993, 2.8435) (35.7023, 2.8356) (36.0054, 2.8276) (36.3085, 2.8195) (36.6117, 2.8114) (36.9148, 2.803) (37.218, 2.7946) (37.5211, 2.786) (37.8242, 2.7772) (38.1273, 2.7683) (38.4303, 2.7592) (38.7334, 2.75) (39.0364, 2.7406) (39.3394, 2.7312) (39.6425, 2.7216) (39.9456, 2.7119) (40.2488, 2.7021) (40.552, 2.6922) (40.8552, 2.6823) (41.1585, 2.6722) (41.4618, 2.662) (41.7651, 2.6518) (42.0683, 2.6413) (42.3716, 2.6308) (42.6748, 2.6201) (42.9781, 2.6092) (43.2813, 2.5981) (43.5845, 2.5869) (43.8878, 2.5756) (44.191, 2.5641) (44.4943, 2.5525) (44.7975, 2.5409) (45.1007, 2.5291) (45.4039, 2.5174) (45.7071, 2.5055) (46.0103, 2.4937) (46.3135, 2.4817) (46.6168, 2.4697) (46.92, 2.4576) (47.2234, 2.4453) (47.5268, 2.433) (47.8302, 2.4205) (48.1336, 2.4079) (48.4371, 2.3952) (48.7405, 2.3824) (49.0439, 2.3695) (49.3473, 2.3565) (49.6507, 2.3435) (49.954, 2.3303) (50.2574, 2.3171) (50.5607, 2.3038) (50.8641, 2.2904) (51.1675, 2.277) (51.4709, 2.2636) (51.7743, 2.2501) (52.0777, 2.2366) (52.3812, 2.223) (52.6847, 2.2093) (52.9881, 2.1955) (53.2916, 2.1816) (53.5951, 2.1675) (53.8985, 2.1533) (54.2019, 2.139) (54.5054, 2.1246) (54.8088, 2.1102) (55.1123, 2.0959) (55.4158, 2.0815) (55.7193, 2.0672) (56.0229, 2.0528) (56.3264, 2.0383) (56.63, 2.0237) (56.9336, 2.0089) (57.2371, 1.9939) (57.5406, 1.9789) (57.8441, 1.9637) (58.1477, 1.9486) (58.4512, 1.9336) (58.7547, 1.9186) (59.0582, 1.9037) (59.3617, 1.8887) (59.6652, 1.8737) (59.9688, 1.8586) (60.2723, 1.8433) (60.5759, 1.8278) (60.8795, 1.8122) (61.1831, 1.7965) (61.4867, 1.7809) (61.7904, 1.7652) (62.0941, 1.7496) (62.3978, 1.7341) (62.7015, 1.7186) (63.0052, 1.7031) (63.3089, 1.6875) (63.6126, 1.6717) (63.9163, 1.6559) (64.22, 1.6399) (64.5237, 1.6239) (64.8273, 1.6079) (65.131, 1.5919) (65.4347, 1.5759) (65.7384, 1.56) (66.0421, 1.5441) (66.3458, 1.5282) (66.6495, 1.5122) (66.9532, 1.4963) (67.2568, 1.4802) (67.5605, 1.4641) (67.8641, 1.448) (68.1678, 1.4318) (68.4716, 1.4155) (68.7754, 1.3993) (69.0793, 1.383) (69.3832, 1.3667) (69.6871, 1.3504) (69.991, 1.3341) (70.2949, 1.3178) (70.5987, 1.3015) (70.9026, 1.2852) (71.2065, 1.2689) (71.5103, 1.2526) (71.8141, 1.2363) (72.118, 1.22) (72.4218, 1.2038) (72.7257, 1.1875) (73.0296, 1.1712) (73.3335, 1.1549) (73.6374, 1.1385) (73.9413, 1.1222) (74.2451, 1.1059) (74.549, 1.0896) (74.8528, 1.0733) (75.1566, 1.0571) (75.4604, 1.041) (75.7642, 1.0249) (76.068, 1.0088) (76.3717, 0.9927) (76.6755, 0.9766) (76.9793, 0.9605) (77.2831, 0.9444) (77.5869, 0.9282) (77.8907, 0.9121) (78.1944, 0.896) (78.4981, 0.88) (78.8018, 0.8639) (79.1054, 0.848) (79.4089, 0.8321) (79.7125, 0.8162) (80.0161, 0.8003) (80.3196, 0.7845) (80.6232, 0.7687) (80.9268, 0.7529) (81.2304, 0.7371) (81.5341, 0.7215) (81.8377, 0.7059) (82.1413, 0.6903) (82.4448, 0.6749) (82.7484, 0.6595) (83.0518, 0.6442) (83.3552, 0.629) (83.6585, 0.6139) (83.9618, 0.5988) (84.265, 0.5837) (84.5682, 0.5687) (84.8714, 0.5538) (85.1746, 0.5389) (85.4778, 0.5241) (85.781, 0.5093) (86.0842, 0.4947) (86.3873, 0.4801) (86.6904, 0.4657) (86.9935, 0.4514) (87.2965, 0.4372) (87.5995, 0.4233) (87.9025, 0.4095) (88.2054, 0.3959) (88.5083, 0.3825) (88.8112, 0.3692) (89.114, 0.3561) (89.4167, 0.3432) (89.7193, 0.3304) (90.0218, 0.3176) (90.3242, 0.305) (90.6266, 0.2925) (90.929, 0.2801) (91.2315, 0.268) (91.5341, 0.256) (91.8367, 0.2443) (92.1392, 0.2329) (92.4415, 0.2217) (92.7434, 0.2109) (93.0449, 0.2003) (93.3459, 0.19) (93.6466, 0.18) (93.9473, 0.1703) (94.2481, 0.161) (94.5494, 0.152) (94.8511, 0.1433) (95.1529, 0.135) (95.4543, 0.1271) (95.7544, 0.1196) (96.0526, 0.1124) (96.3484, 0.1058) (96.6419, 0.0996) (96.9336, 0.0939) (97.2249, 0.0888) (97.5167, 0.0844) (97.8092, 0.0806) (98.1019, 0.0775) (98.3924, 0.0752) (98.6765, 0.0736) (98.9495, 0.0728) (99.2063, 0.0727) (99.4426, 0.0732) (99.6555, 0.0744) (99.806, 0.0759) (99.9074, 0.0773) (99.97, 0.0784) (100, 0.079) knots 0 0 0 0 0 0 0.00142857 0.00285714 0.00428571 0.00571429 0.00714286 0.00857143 0.01 0.01142857 0.01285714 0.01428571 0.01571429 0.01714286 0.01857143 0.02 0.02142857 0.02285714 0.02428571 0.02571429 0.02714286 0.02857143 0.03 0.03142857 0.03285714 0.03428571 0.03571429 0.03714286 0.03857143 0.04 0.04142857 0.04285714 0.04428571 0.04571429 0.04714286 0.04857143 0.05 0.05142857 0.05285714 0.05428571 0.05571429 0.05714286 0.05857143 0.06 0.06142857 0.06285714 0.06428571 0.06571429 0.06714286 0.06857143 0.07 0.07142857 0.07285714 0.07428571 0.07571429 0.07714286 0.07857143 0.08 0.08142857 0.08285714 0.08428571 0.08571429 0.08714286 0.08857143 0.09 0.09142857 0.09285714 0.09428571 0.09571429 0.09714286 0.09857143 0.1 0.10142857 0.10285714 0.10428571 0.10571429 0.10714286 0.10857143 0.11 0.11142857 0.11285714 0.11428571 0.11571429 0.11714286 0.11857143 0.12 0.12142857 0.12285714 0.12428571 0.12571429 0.12714286 0.12857143 0.13 0.13142857 0.13285714 0.13428571 0.13571429 0.13714286 0.13857143 0.14 0.14142857 0.14285714 0.14428571 0.14571429 0.14714286 0.14857143 0.15 0.15142857 0.15285714 0.15428571 0.15571429 0.15714286 0.15857143 0.16 0.16142857 0.16285714 0.16428571 0.16571429 0.16714286 0.16857143 0.17 0.17142857 0.17285714 0.17428571 0.17571429 0.17714286 0.17857143 0.18 0.18142857 0.18285714 0.18428571 0.18571429 0.18714286 0.18857143 0.19 0.19142857 0.19285714 0.19428571 0.19571429 0.19714286 0.19857143 0.2 0.20142857 0.20285714 0.20428571 0.20571429 0.20714286 0.20857143 0.21 0.21142857 0.21285714 0.21428571 0.21571429 0.21714286 0.21857143 0.22 0.22142857 0.22285714 0.22428571 0.22571429 0.22714286 0.22857143 0.23 0.23142857 0.23285714 0.23428571 0.23571429 0.23714286 0.23857143 0.24 0.24142857 0.24285714 0.24428571 0.24571429 0.24714286 0.24857143 0.25 0.25142857 0.25285714 0.25428571 0.25571429 0.25714286 0.25857143 0.26 0.26142857 0.26285714 0.26428571 0.26571429 0.26714286 0.26857143 0.27 0.27142857 0.27285714 0.27428571 0.27571429 0.27714286 0.27857143 0.28 0.28142857 0.28285714 0.28428571 0.28571429 0.28714286 0.28857143 0.29 0.29142857 0.29285714 0.29428571 0.29571429 0.29714286 0.29857143 0.3 0.30142857 0.30285714 0.30428571 0.30571429 0.30714286 0.30857143 0.31 0.31142857 0.31285714 0.31428571 0.31571429 0.31714286 0.31857143 0.32 0.32142857 0.32285714 0.32428571 0.32571429 0.32714286 0.32857143 0.33 0.33142857 0.33285714 0.33428571 0.33571429 0.33714286 0.33857143 0.34 0.34142857 0.34285714 0.34428571 0.34571429 0.34714286 0.34857143 0.35 0.35142857 0.35285714 0.35428571 0.35571429 0.35714286 0.35857143 0.36 0.36142857 0.36285714 0.36428571 0.36571429 0.36714286 0.36857143 0.37 0.37142857 0.37285714 0.37428571 0.37571429 0.37714286 0.37857143 0.38 0.38142857 0.38285714 0.38428571 0.38571429 0.38714286 0.38857143 0.39 0.39142857 0.39285714 0.39428571 0.39571429 0.39714286 0.39857143 0.4 0.40142857 0.40285714 0.40428571 0.40571429 0.40714286 0.40857143 0.41 0.41142857 0.41285714 0.41428571 0.41571429 0.41714286 0.41857143 0.42 0.42142857 0.42285714 0.42428571 0.42571429 0.42714286 0.42857143 0.43 0.43142857 0.43285714 0.43428571 0.43571429 0.43714286 0.43857143 0.44 0.44142857 0.44285714 0.44428571 0.44571429 0.44714286 0.44857143 0.45 0.45142857 0.45285714 0.45428571 0.45571429 0.45714286 0.45857143 0.46 0.46142857 0.46285714 0.46428571 0.46571429 0.46714286 0.46857143 0.47 0.47142857 0.47285714 0.47428571 0.47571429 0.47714286 0.47857143 0.48 0.48142857 0.48285714 0.48428571 0.48571429 0.48714286 0.48857143 0.49 0.49142857 0.49285714 0.49428571 0.49571429 0.49714286 0.49857143 0.5 0.50142857 0.50285714 0.50428571 0.50571429 0.50714286 0.50857143 0.51 0.51142857 0.51285714 0.51428571 0.51571429 0.51714286 0.51857143 0.52 0.52142857 0.52285714 0.52428571 0.52571429 0.52714286 0.52857143 0.53 0.53142857 0.53285714 0.53428571 0.53571429 0.53714286 0.53857143 0.54 0.54142857 0.54285714 0.54428571 0.54571429 0.54714286 0.54857143 0.55 0.55142857 0.55285714 0.55428571 0.55571429 0.55714286 0.55857143 0.56 0.56142857 0.56285714 0.56428571 0.56571429 0.56714286 0.56857143 0.57 0.57142857 0.57285714 0.57428571 0.57571429 0.57714286 0.57857143 0.58 0.58142857 0.58285714 0.58428571 0.58571429 0.58714286 0.58857143 0.59 0.59142857 0.59285714 0.59428571 0.59571429 0.59714286 0.59857143 0.6 0.60142857 0.60285714 0.60428571 0.60571429 0.60714286 0.60857143 0.61 0.61142857 0.61285714 0.61428571 0.61571429 0.61714286 0.61857143 0.62 0.62142857 0.62285714 0.62428571 0.62571429 0.62714286 0.62857143 0.63 0.63142857 0.63285714 0.63428571 0.63571429 0.63714286 0.63857143 0.64 0.64142857 0.64285714 0.64428571 0.64571429 0.64714286 0.64857143 0.65 0.65142857 0.65285714 0.65428571 0.65571429 0.65714286 0.65857143 0.66 0.66142857 0.66285714 0.66428571 0.66571429 0.66714286 0.66857143 0.67 0.67142857 0.67285714 0.67428571 0.67571429 0.67714286 0.67857143 0.68 0.68142857 0.68285714 0.68428571 0.68571429 0.68714286 0.68857143 0.69 0.69142857 0.69285714 0.69428571 0.69571429 0.69714286 0.69857143 0.7 0.70142857 0.70285714 0.70428571 0.70571429 0.70714286 0.70857143 0.71 0.71142857 0.71285714 0.71428571 0.71571429 0.71714286 0.71857143 0.72 0.72142857 0.72285714 0.72428571 0.72571429 0.72714286 0.72857143 0.73 0.73142857 0.73285714 0.73428571 0.73571429 0.73714286 0.73857143 0.74 0.74142857 0.74285714 0.74428571 0.74571429 0.74714286 0.74857143 0.75 0.75142857 0.75285714 0.75428571 0.75571429 0.75714286 0.75857143 0.76 0.76142857 0.76285714 0.76428571 0.76571429 0.76714286 0.76857143 0.77 0.77142857 0.77285714 0.77428571 0.77571429 0.77714286 0.77857143 0.78 0.78142857 0.78285714 0.78428571 0.78571429 0.78714286 0.78857143 0.79 0.79142857 0.79285714 0.79428571 0.79571429 0.79714286 0.79857143 0.8 0.80142857 0.80285714 0.80428571 0.80571429 0.80714286 0.80857143 0.81 0.81142857 0.81285714 0.81428571 0.81571429 0.81714286 0.81857143 0.82 0.82142857 0.82285714 0.82428571 0.82571429 0.82714286 0.82857143 0.83 0.83142857 0.83285714 0.83428571 0.83571429 0.83714286 0.83857143 0.84 0.84142857 0.84285714 0.84428571 0.84571429 0.84714286 0.84857143 0.85 0.85142857 0.85285714 0.85428571 0.85571429 0.85714286 0.85857143 0.86 0.86142857 0.86285714 0.86428571 0.86571429 0.86714286 0.86857143 0.87 0.87142857 0.87285714 0.87428571 0.87571429 0.87714286 0.87857143 0.88 0.88142857 0.88285714 0.88428571 0.88571429 0.88714286 0.88857143 0.89 0.89142857 0.89285714 0.89428571 0.89571429 0.89714286 0.89857143 0.9 0.90142857 0.90285714 0.90428571 0.90571429 0.90714286 0.90857143 0.91 0.91142857 0.91285714 0.91428571 0.91571429 0.91714286 0.91857143 0.92 0.92142857 0.92285714 0.92428571 0.92571429 0.92714286 0.92857143 0.93 0.93142857 0.93285714 0.93428571 0.93571429 0.93714286 0.93857143 0.94 0.94142857 0.94285714 0.94428571 0.94571429 0.94714286 0.94857143 0.95 0.95142857 0.95285714 0.95428571 0.95571429 0.95714286 0.95857143 0.96 0.96142857 0.96285714 0.96428571 0.96571429 0.96714286 0.96857143 0.97 0.97142857 0.97285714 0.97428571 0.97571429 0.97714286 0.97857143 0.98 0.98142857 0.98285714 0.98428571 0.98571429 0.98714286 0.98857143 0.99 0.99142857 0.99285714 0.99428571 0.99571429 0.99714286 0.99857143 1 1 1 1 1 1
  line L0 (100, 0.079) -> (100, -0.079)
  point P0 (99.317, -0.149)
  point P1 (97.976, -0.302)
  point P2 (96.433, -0.493)
  point P3 (94.814, -0.699)
  point P4 (93.177, -0.911)
  point P5 (91.532, -1.125)
  point P6 (89.887, -1.34)
  point P7 (88.242, -1.553)
  point P8 (86.598, -1.765)
  point P9 (84.956, -1.975)
  point P10 (83.314, -2.181)
  point P11 (81.673, -2.385)
  point P12 (80.034, -2.585)
  point P13 (78.394, -2.782)
  point P14 (76.755, -2.974)
  point P15 (75.116, -3.162)
  point P16 (73.477, -3.346)
  point P17 (71.84, -3.525)
  point P18 (70.202, -3.698)
  point P19 (68.564, -3.866)
  point P20 (66.926, -4.029)
  point P21 (65.289, -4.186)
  point P22 (63.651, -4.337)
  point P23 (62.013, -4.481)
  point P24 (60.374, -4.621)
  point P25 (58.735, -4.753)
  point P26 (57.096, -4.88)
  point P27 (55.457, -5.001)
  point P28 (53.817, -5.115)
  point P29 (52.177, -5.224)
  point P30 (50.537, -5.325)
  point P31 (48.897, -5.42)
  point P32 (47.258, -5.509)
  point P33 (45.619, -5.591)
  point P34 (43.98, -5.665)
  point P35 (42.342, -5.732)
  point P36 (40.705, -5.791)
  point P37 (39.069, -5.841)
  point P38 (37.435, -5.883)
  point P39 (35.802, -5.915)
  point P40 (34.17, -5.938)
  point P41 (32.54, -5.951)
  point P42 (30.912, -5.952)
  point P43 (29.286, -5.942)
  point P44 (27.663, -5.92)
  point P45 (26.044, -5.885)
  point P46 (24.428, -5.835)
  point P47 (22.816, -5.771)
  point P48 (21.21, -5.69)
  point P49 (19.611, -5.591)
  point P50 (18.02, -5.473)
  point P51 (16.438, -5.333)
  point P52 (14.868, -5.17)
  point P53 (13.311, -4.98)
  point P54 (11.772, -4.762)
  point P55 (10.256, -4.512)
  point P56 (8.767, -4.226)
  point P57 (7.316, -3.901)
  point P58 (5.92, -3.533)
  point P59 (4.605, -3.123)
  point P60 (3.414, -2.677)
  point P61 (2.411, -2.224)
  point P62 (1.642, -1.801)
  point P63 (1.093, -1.435)
  point P64 (0.71, -1.124)
  point P65 (0.44, -0.856)
  point P66 (0.248, -0.619)
  point P67 (0.117, -0.406)
  point P68 (0.034, -0.209)
  point P69 (0.001, -0.027)
  point P70 (0.02, 0.151)
  point P71 (0.106, 0.329)
  point P72 (0.255, 0.501)
  point P73 (0.467, 0.671)
  point P74 (0.752, 0.85)
  point P75 (1.142, 1.045)
  point P76 (1.688, 1.263)
  point P77 (2.463, 1.51)
  point P78 (3.51, 1.769)
  point P79 (4.791, 2.013)
  point P80 (6.217, 2.224)
  point P81 (7.72, 2.4)
  point P82 (9.265, 2.545)
  point P83 (10.837, 2.662)
  point P84 (12.427, 2.758)
  point P85 (14.03, 2.834)
  point P86 (15.642, 2.893)
  point P87 (17.261, 2.939)
  point P88 (18.887, 2.971)
  point P89 (20.517, 2.993)
  point P90 (22.151, 3.005)
  point P91 (23.789, 3.009)
  point P92 (25.428, 3.004)
  point P93 (27.07, 2.993)
  point P94 (28.713, 2.974)
  point P95 (30.359, 2.95)
  point P96 (32.005, 2.92)
  point P97 (33.653, 2.886)
  point P98 (35.301, 2.846)
  point P99 (36.951, 2.802)
  point P100 (38.601, 2.754)
  point P101 (40.251, 2.702)
  point P102 (41.903, 2.647)
  point P103 (43.555, 2.588)
  point P104 (45.207, 2.525)
  point P105 (46.859, 2.46)
  point P106 (48.513, 2.392)
  point P107 (50.167, 2.321)
  point P108 (51.821, 2.248)
  point P109 (53.476, 2.173)
  point P110 (55.131, 2.095)
  point P111 (56.787, 2.016)
  point P112 (58.443, 1.934)
  point P113 (60.099, 1.852)
  point P114 (61.756, 1.767)
  point P115 (63.414, 1.682)
  point P116 (65.072, 1.595)
  point P117 (66.73, 1.508)
  point P118 (68.388, 1.42)
  point P119 (70.048, 1.331)
  point P120 (71.708, 1.242)
  point P121 (73.368, 1.153)
  point P122 (75.028, 1.064)
  point P123 (76.687, 0.976)
  point P124 (78.346, 0.888)
  point P125 (80.003, 0.801)
  point P126 (81.66, 0.715)
  point P127 (83.316, 0.631)
  point P128 (84.969, 0.549)
  point P129 (86.621, 0.469)
  point P130 (88.271, 0.393)
  point P131 (89.918, 0.322)
  point P132 (91.562, 0.255)
  point P133 (93.201, 0.195)
  point P134 (94.829, 0.144)
  point P135 (96.436, 0.104)
  point P136 (97.97, 0.079)
  point P137 (99.314, 0.073)
surface "Profilschnitt_R2" add patch profiles "Skizze6" section 1 separate body makes body 6
scale "Profiltiefe_R2" factor 1.8 about (0, 0, 0) bodies 6
move_body "Station_R2" bodies 6 to x (1, 0, 0) y (0, 1, 0) z (0, 0, 1) at (0, 669.9071, 10.646)